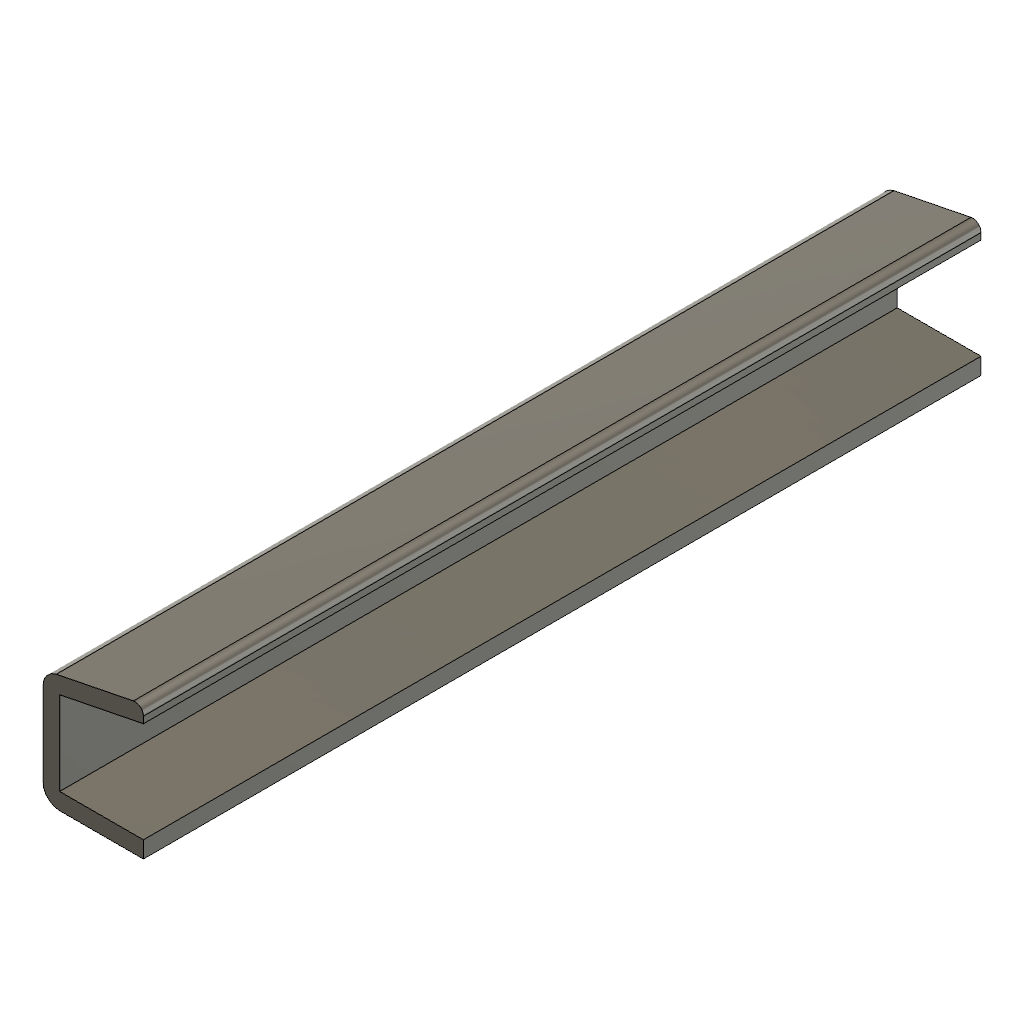
rc-airplanes-trainer-airplane-fusion-parts-wind-band-clip-rear (Autodesk Fusion 360 design; units mm, degrees)
Autodesk Fusion 360 part; units mm, degrees
sketch "Sketch1" plane through (0, 0, 0) normal (0, 0, 1) x (1, 0, 0)
  line L0 (5, -5) -> (-5, -5)
  line L1 (-5, -5) -> (-5, 5)
  line L2 (5, -5) -> (-5, 5) construction
  line L3 (-5, -5) -> (5, 5) construction
  line L4 (5, 7) -> (-5, 5)
  line L5 (5, 7) -> (5, 7.7802)
  line L6 (3.8039, 8.7608) -> (-5, 7)
  line L7 (5, -5) -> (5, -7)
  line L8 (5, -7) -> (-5, -7)
  line L9 (-7, -5) -> (-7, 4.9604)
  line L10 (-5, 7) -> (-5.3922, 6.9216)
  line L11 (5, 7) -> (5, 7.7802)
  arc A0 (-5.3922, 6.9216) -> (-7, 4.9604) centre (-5, 4.9604) ccw
  arc A1 (-7, -5) -> (-5, -7) centre (-5, -5) ccw
  arc A2 (5, 7.7802) -> (3.8039, 8.7608) centre (4, 7.7802) ccw
  point P0 (-7, -7)
  dimension "d1" = 10
  dimension "d2" = 10
  dimension "d3" = 2
  dimension "d6" = 2
  dimension "d7" = 2
  dimension "d8" = 12
  dimension "d9" = 2
  dimension "d10" = 2
  dimension "d11" = 1
  constraint horizontal L0
  constraint perpendicular L0 L1
  constraint coincident L2 origin
  constraint coincident L3 origin
  constraint perpendicular L0 L7
  constraint perpendicular L7 L8
  constraint perpendicular L8 L9
  constraint parallel L6 L10
  constraint tangent L10 A0
  constraint tangent L9 A0
  constraint coincident P0 L9
  constraint coincident P0 L8
  constraint tangent L9 A1
  constraint tangent L8 A1
  constraint tangent L6 A2
  constraint tangent L5 A2
  measures "d1" distance of L1.end L3.end
  measures "d2" distance of L0.end L1.end
  measures "d3" distance of L3.end L4.start
  measures "d6" distance of L1.end L6.end
  measures "d7" distance of L0.start L7.end
  measures "d8" distance of L7.end P0
  measures "d9" radius of A0
  measures "d10" radius of A1
  measures "d11" radius of A2
extrude "Extrude1" add sketch "Sketch1" along normal blind 90
extrude "Extrude2" cut 1 faces at (1.268, 6.9203, 90) along direction (0, 0, -1) blind 80
extrude "Extrude3" add 1 faces at (1.268, 6.9203, 10) along direction (0, 0, 1) blind 80
extrude "Extrude4" add 1 faces at (1.268, 6.9203, 90) along direction (0, 0, 1) blind 10
